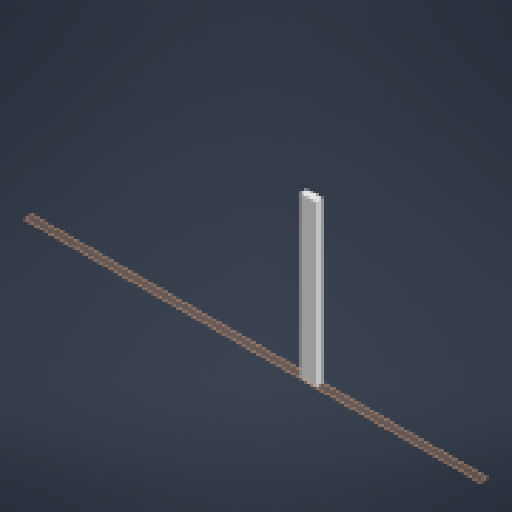
# Autodesk Inventor part: 2x4x34
Saved by Autodesk Inventor 2027 (Build 310192000, 192)
## iProperties
Created: 2026-10-18
Part Number: 2x4x34
Material: Generic
Document SubType Name: Modeling
Designer: lucas
Density: 1 g/cm^3
Appearance: Default
Author: lucas
Autodesk Inventor part; units mm, degrees
ref_plane "YZ Plane" through (0, 0, 0) normal (1, 0, 0) x (0, 1, 0)
ref_plane "XZ Plane" through (0, 0, 0) normal (0, 1, 0) x (-1, 0, 0)
ref_plane "XY Plane" through (0, 0, 0) normal (0, 0, 1) x (1, 0, 0)
ref_plane "Work Plane1" through (-1117.6, 44.45, 0) normal (0, 1, 0) x (1, 0, 0)
sketch "Sketch1" plane through (-1117.6, 44.45, 0) normal (0, 1, 0) x (1, 0, 0)
  line L0 (1371.6, 0) -> (1460.5, 0)
  line L1 (1460.5, 0) -> (1460.5, 38.1)
  line L2 (1460.5, 38.1) -> (1371.6, 38.1)
  line L3 (1371.6, 38.1) -> (1371.6, 0)
  point P0 (1117.6, 0)
  point P1 (1460.5, 0)
  point P2 (1371.6, 38.1)
  constraints: 8 end point, 2 parallel, 1 horizontal, 1 perpendicular, 4 other
extrude "Extrusion1" add sketch "Sketch1" along normal blind 863.6
body "Solid1"
